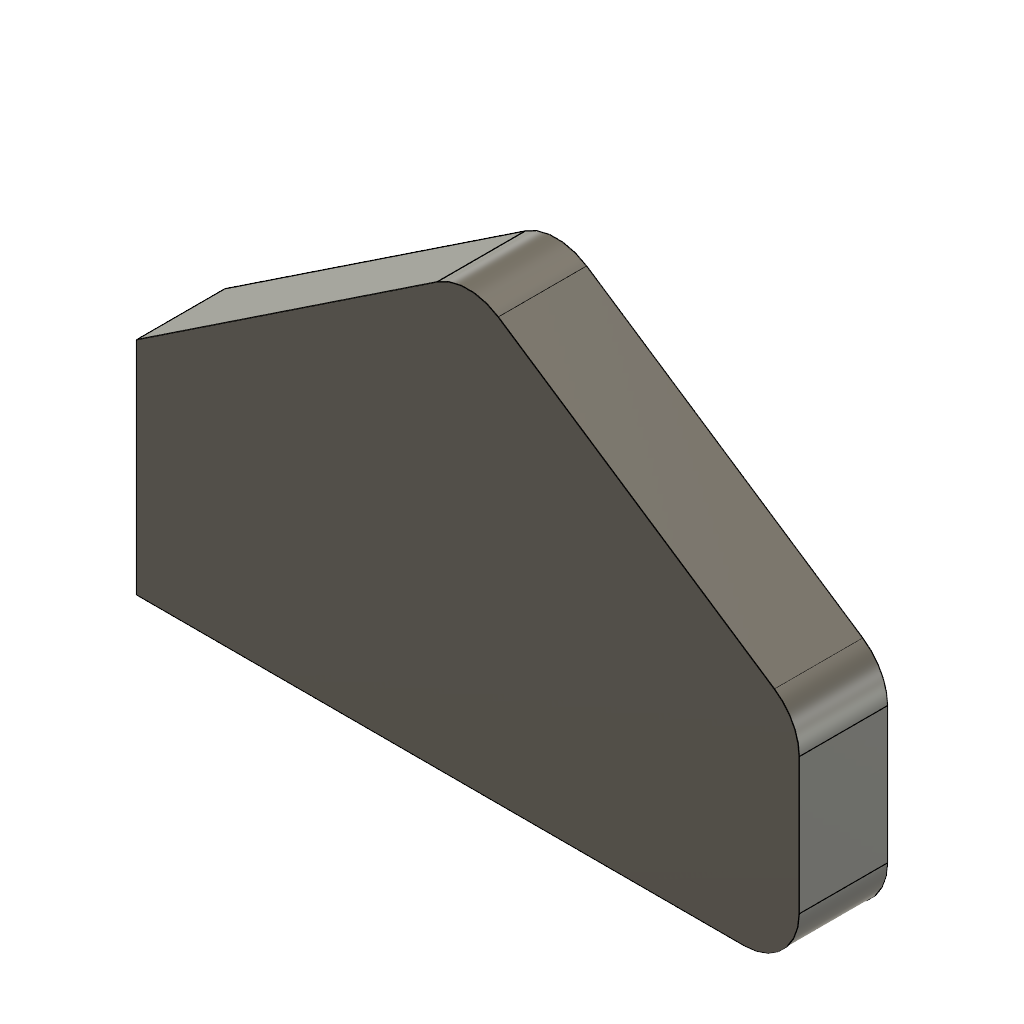
sk_fillet_corners (Autodesk Fusion 360 design; units mm, degrees)
part number: 2026-11-13-14-35-03-582
Autodesk Fusion 360 part; units mm, degrees
sketch "Sketch1" plane through (0, 0, 0) normal (0, 0, 1) x (1, 0, 0)
  line L0 (0, 0) -> (27.5, 0)
  line L1 (30, 2.5) -> (30, 8.662)
  line L2 (28.8868, 10.7422) -> (16.3868, 19.0755)
  line L3 (13.6132, 19.0755) -> (0, 10)
  line L4 (0, 10) -> (0, 0)
  arc A0 (27.5, 0) -> (30, 2.5) centre (27.5, 2.5) ccw
  arc A1 (30, 8.662) -> (28.8868, 10.7422) centre (27.5, 8.662) ccw
  arc A2 (16.3868, 19.0755) -> (13.6132, 19.0755) centre (15, 16.9954) ccw
  constraint tangent L0 A0
  constraint tangent L1 A0
  constraint tangent L1 A1
  constraint tangent L2 A1
  constraint tangent L2 A2
  constraint tangent L3 A2
extrude "Extrude1" add sketch "Sketch1" along normal blind 4
